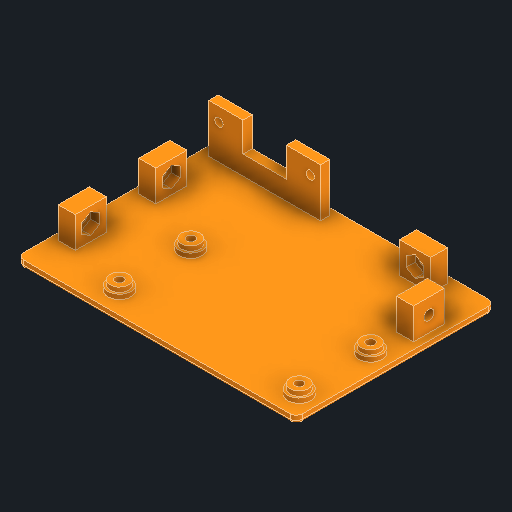
# Autodesk Inventor part: base_plate_compact_orange
Saved by Autodesk Inventor 2027.1 (Build 311270010, 270A)
## iProperties
Created: 2026-10-29
Part Number: base_plate_compact_orange
Material: Generic
Document SubType Name: Modeling
Designer: alexg
Density: 1 g/cm^3
Appearance: Orange
Description: COPY of base_plate_compact, orange: through bolts + hex nuts; back side +4 mm to match the frame copy (USB socket bracket + tab B moved with the wall)
Mass: 17.4421 g
Surface Area: 151.967 cm^2
Volume: 17.4421 cm^3
Author: alexg
Autodesk Inventor part; units mm, degrees
ref_plane "Work Plane1" through (0, -31.66, 0) normal (0, 1, 0) x (-1, 0, 0)
sketch "Plate sketch" plane through (0, -31.66, 0) normal (0, 1, 0) x (-1, 0, 0)
  line L0 (45, -30) -> (-45, -30)
  line L1 (-45, -30) -> (-45, 30)
  line L2 (-45, 30) -> (45, 30)
  line L3 (45, 30) -> (45, -30)
  constraints: 8 end point, 2 parallel, 1 horizontal, 1 perpendicular
extrude "Plate" add sketch "Plate sketch" against normal blind 2.5
ref_plane "Work Plane2" through (0, -31.66, 0) normal (0, 1, 0) x (-1, 0, 0)
sketch "Pi standoffs sketch" plane through (0, -31.66, 0) normal (0, 1, 0) x (-1, 0, 0)
  circle A0 centre (-38.97, 0.03) radius 3
  circle A1 centre (19.03, 0.03) radius 3
  circle A2 centre (-38.97, 23.03) radius 3
  circle A3 centre (19.03, 23.03) radius 3
  constraints: 4 centre point
extrude "Pi standoffs" add sketch "Pi standoffs sketch" along normal blind 3
ref_plane "Work Plane11" through (0, -31.66, 0) normal (0, 1, 0) x (-1, 0, 0)
sketch "Pi standoff feet (cover the nut pockets) sketch" plane through (0, -31.66, 0) normal (0, 1, 0) x (-1, 0, 0)
  circle A0 centre (-38.97, 0.03) radius 3.7
  circle A1 centre (19.03, 0.03) radius 3.7
  circle A2 centre (-38.97, 23.03) radius 3.7
  circle A3 centre (19.03, 23.03) radius 3.7
  constraints: 4 centre point
extrude "Pi standoff feet (cover the nut pockets)" add sketch "Pi standoff feet (cover the nut pockets) sketch" along normal blind 1.5
ref_plane "Work Plane3" through (0, -28.66, 0) normal (0, 1, 0) x (-1, 0, 0)
sketch "M2.5 insert holes (Pi) sketch" plane through (0, -28.66, 0) normal (0, 1, 0) x (-1, 0, 0)
  circle A0 centre (-38.97, 0.03) radius 1.35
  circle A1 centre (19.03, 0.03) radius 1.35
  circle A2 centre (-38.97, 23.03) radius 1.35
  circle A3 centre (19.03, 23.03) radius 1.35
  constraints: 4 centre point
extrude "M2.5 bolt holes (Pi, 2.7 through)" cut sketch "M2.5 insert holes (Pi) sketch" against normal blind 6
ref_plane "Work Plane4" through (0, -31.66, 0) normal (0, 1, 0) x (-1, 0, 0)
sketch "Screw tabs sketch" plane through (0, -31.66, 0) normal (0, 1, 0) x (-1, 0, 0)
  line L0 (42.8, -17) -> (39.8, -17)
  line L1 (39.8, -17) -> (39.8, -7)
  line L2 (39.8, -7) -> (42.8, -7)
  line L3 (42.8, -7) -> (42.8, -17)
  line L4 (42.8, 9) -> (39.8, 9)
  line L5 (39.8, 9) -> (39.8, 19)
  line L6 (39.8, 19) -> (42.8, 19)
  line L7 (42.8, 19) -> (42.8, 9)
  line L8 (-39.8, -20) -> (-42.8, -20)
  line L9 (-42.8, -20) -> (-42.8, -10)
  line L10 (-42.8, -10) -> (-39.8, -10)
  line L11 (-39.8, -10) -> (-39.8, -20)
  line L12 (-22, -27.8) -> (-32, -27.8)
  line L13 (-32, -27.8) -> (-32, -24.8)
  line L14 (-32, -24.8) -> (-22, -24.8)
  line L15 (-22, -24.8) -> (-22, -27.8)
  constraints: 32 end point, 8 parallel, 4 horizontal, 4 perpendicular
extrude "Screw tabs" add sketch "Screw tabs sketch" along normal blind 10
ref_plane "Work Plane12" through (0, -31.66, 0) normal (0, 1, 0) x (-1, 0, 0)
sketch "Screw tabs thickened to 5.5 (nut pockets) sketch" plane through (0, -31.66, 0) normal (0, 1, 0) x (-1, 0, 0)
  line L0 (39.8, -17) -> (37.3, -17)
  line L1 (37.3, -17) -> (37.3, -7)
  line L2 (37.3, -7) -> (39.8, -7)
  line L3 (39.8, -7) -> (39.8, -17)
  line L4 (39.8, 9) -> (37.3, 9)
  line L5 (37.3, 9) -> (37.3, 19)
  line L6 (37.3, 19) -> (39.8, 19)
  line L7 (39.8, 19) -> (39.8, 9)
  line L8 (-37.3, -20) -> (-39.8, -20)
  line L9 (-39.8, -20) -> (-39.8, -10)
  line L10 (-39.8, -10) -> (-37.3, -10)
  line L11 (-37.3, -10) -> (-37.3, -20)
  line L12 (-22, -24.8) -> (-32, -24.8)
  line L13 (-32, -24.8) -> (-32, -22.3)
  line L14 (-32, -22.3) -> (-22, -22.3)
  line L15 (-22, -22.3) -> (-22, -24.8)
  constraints: 32 end point, 8 parallel, 4 horizontal, 4 perpendicular
extrude "Screw tabs thickened to 5.5 (nut pockets)" add sketch "Screw tabs thickened to 5.5 (nut pockets) sketch" along normal blind 10
ref_plane "Work Plane5" through (-43.5, 0, 0) normal (1, 0, 0) x (0, 1, 0)
sketch "M3 insert holes L sketch" plane through (-43.5, 0, 0) normal (1, 0, 0) x (0, 1, 0)
  circle A0 centre (-26.66, -12) radius 1.6
  circle A1 centre (-26.66, 14) radius 1.6
  constraints: 2 centre point
extrude "M3 bolt holes L (3.2)" cut sketch "M3 insert holes L sketch" along normal blind 7
ref_plane "Work Plane6" through (43.5, 0, 0) normal (1, 0, 0) x (0, 1, 0)
sketch "M3 insert holes R sketch" plane through (43.5, 0, 0) normal (1, 0, 0) x (0, 1, 0)
  circle A0 centre (-26.66, -15) radius 1.6
  constraints: 1 centre point
extrude "M3 bolt holes R (3.2)" cut sketch "M3 insert holes R sketch" against normal blind 7
ref_plane "Work Plane7" through (0, 0, -28.5) normal (0, 0, 1) x (1, 0, 0)
sketch "M3 insert hole B sketch" plane through (0, 0, -28.5) normal (0, 0, 1) x (1, 0, 0)
  circle A0 centre (27, -26.66) radius 1.6
  constraints: 1 centre point
extrude "M3 bolt hole B (3.2)" cut sketch "M3 insert hole B sketch" along normal blind 7
ref_plane "Work Plane8" through (0, -31.66, 0) normal (0, 1, 0) x (-1, 0, 0)
sketch "USB socket bracket sketch" plane through (0, -31.66, 0) normal (0, 1, 0) x (-1, 0, 0)
  line L0 (40, -27.8) -> (8, -27.8)
  line L1 (8, -27.8) -> (8, -24.8)
  line L2 (8, -24.8) -> (40, -24.8)
  line L3 (40, -24.8) -> (40, -27.8)
  constraints: 8 end point, 2 parallel, 1 horizontal, 1 perpendicular
extrude "USB socket bracket" [suppressed]
ref_plane "Work Plane9" through (0, 0, -27.8) normal (0, 0, 1) x (1, 0, 0)
sketch "External plug opening sketch" plane through (0, 0, -27.8) normal (0, 0, 1) x (1, 0, 0)
  line L0 (-31, -30.84) -> (-17, -30.84)
  line L1 (-17, -30.84) -> (-17, -19.84)
  line L2 (-17, -19.84) -> (-31, -19.84)
  line L3 (-31, -19.84) -> (-31, -30.84)
  constraints: 8 end point, 2 parallel, 1 horizontal, 1 perpendicular
extrude "External plug opening" [suppressed]
ref_plane "Work Plane10" through (0, 0, -24.8) normal (0, 0, 1) x (1, 0, 0)
sketch "M2.5x3 insert holes (USB) sketch" plane through (0, 0, -24.8) normal (0, 0, 1) x (1, 0, 0)
  circle A0 centre (-36.5, -25.84) radius 1.35
  circle A1 centre (-11.5, -25.84) radius 1.35
  constraints: 2 centre point
extrude "M2.5 bolt holes (USB socket, 2.7)" [suppressed]
ref_plane "Work Plane13" through (0, -34.16, 0) normal (0, 1, 0) x (-1, 0, 0)
sketch "Pi nut pockets M2.5 (underside) sketch" plane through (0, -34.16, 0) normal (0, 1, 0) x (-1, 0, 0)
  line L0 (-41.9722, 0.03) -> (-40.4711, 2.63)
  line L1 (-40.4711, 2.63) -> (-37.4689, 2.63)
  line L2 (-37.4689, 2.63) -> (-35.9678, 0.03)
  line L3 (-35.9678, 0.03) -> (-37.4689, -2.57)
  line L4 (-37.4689, -2.57) -> (-40.4711, -2.57)
  line L5 (-40.4711, -2.57) -> (-41.9722, 0.03)
  line L6 (16.0278, 0.03) -> (17.5289, 2.63)
  line L7 (17.5289, 2.63) -> (20.5311, 2.63)
  line L8 (20.5311, 2.63) -> (22.0322, 0.03)
  line L9 (22.0322, 0.03) -> (20.5311, -2.57)
  line L10 (20.5311, -2.57) -> (17.5289, -2.57)
  line L11 (17.5289, -2.57) -> (16.0278, 0.03)
  line L12 (-41.9722, 23.03) -> (-40.4711, 25.63)
  line L13 (-40.4711, 25.63) -> (-37.4689, 25.63)
  line L14 (-37.4689, 25.63) -> (-35.9678, 23.03)
  line L15 (-35.9678, 23.03) -> (-37.4689, 20.43)
  line L16 (-37.4689, 20.43) -> (-40.4711, 20.43)
  line L17 (-40.4711, 20.43) -> (-41.9722, 23.03)
  line L18 (16.0278, 23.03) -> (17.5289, 25.63)
  line L19 (17.5289, 25.63) -> (20.5311, 25.63)
  line L20 (20.5311, 25.63) -> (22.0322, 23.03)
  line L21 (22.0322, 23.03) -> (20.5311, 20.43)
  line L22 (20.5311, 20.43) -> (17.5289, 20.43)
  line L23 (17.5289, 20.43) -> (16.0278, 23.03)
  constraints: 48 end point
extrude "Pi nut pockets M2.5 (underside)" cut sketch "Pi nut pockets M2.5 (underside) sketch" along normal blind 3.1
ref_plane "Work Plane14" through (-37.3, 0, 0) normal (1, 0, 0) x (0, 1, 0)
sketch "Base nut pockets M3 L sketch" plane through (-37.3, 0, 0) normal (1, 0, 0) x (0, 1, 0)
  line L0 (-23.3691, -12) -> (-25.0146, -14.85)
  line L1 (-25.0146, -14.85) -> (-28.3054, -14.85)
  line L2 (-28.3054, -14.85) -> (-29.9509, -12)
  line L3 (-29.9509, -12) -> (-28.3054, -9.15)
  line L4 (-28.3054, -9.15) -> (-25.0146, -9.15)
  line L5 (-25.0146, -9.15) -> (-23.3691, -12)
  line L6 (-23.3691, 14) -> (-25.0146, 11.15)
  line L7 (-25.0146, 11.15) -> (-28.3054, 11.15)
  line L8 (-28.3054, 11.15) -> (-29.9509, 14)
  line L9 (-29.9509, 14) -> (-28.3054, 16.85)
  line L10 (-28.3054, 16.85) -> (-25.0146, 16.85)
  line L11 (-25.0146, 16.85) -> (-23.3691, 14)
  constraints: 24 end point
extrude "Base nut pockets M3 L" cut sketch "Base nut pockets M3 L sketch" against normal blind 2.9
ref_plane "Work Plane15" through (37.3, 0, 0) normal (1, 0, 0) x (0, 1, 0)
sketch "Base nut pocket M3 R sketch" plane through (37.3, 0, 0) normal (1, 0, 0) x (0, 1, 0)
  line L0 (-23.3691, -15) -> (-25.0146, -17.85)
  line L1 (-25.0146, -17.85) -> (-28.3054, -17.85)
  line L2 (-28.3054, -17.85) -> (-29.9509, -15)
  line L3 (-29.9509, -15) -> (-28.3054, -12.15)
  line L4 (-28.3054, -12.15) -> (-25.0146, -12.15)
  line L5 (-25.0146, -12.15) -> (-23.3691, -15)
  constraints: 12 end point
extrude "Base nut pocket M3 R" cut sketch "Base nut pocket M3 R sketch" along normal blind 2.9
ref_plane "Work Plane16" through (0, 0, -22.3) normal (0, 0, 1) x (1, 0, 0)
sketch "Base nut pocket M3 B sketch" plane through (0, 0, -22.3) normal (0, 0, 1) x (1, 0, 0)
  line L0 (27, -23.3691) -> (24.15, -25.0146)
  line L1 (24.15, -25.0146) -> (24.15, -28.3054)
  line L2 (24.15, -28.3054) -> (27, -29.9509)
  line L3 (27, -29.9509) -> (29.85, -28.3054)
  line L4 (29.85, -28.3054) -> (29.85, -25.0146)
  line L5 (29.85, -25.0146) -> (27, -23.3691)
  constraints: 12 end point
extrude "Base nut pocket M3 B" cut sketch "Base nut pocket M3 B sketch" against normal blind 2.9
ref_plane "Work Plane17" through (-36.5, 0, 0) normal (1, 0, 0) x (0, 1, 0)
sketch "USB countersink 1 (M2.5 flat head, outside face) sketch" plane through (-36.5, 0, 0) normal (1, 0, 0) x (0, 1, 0)
  line L0 (-25.84, -26.65) -> (-25.84, -28)
  line L1 (-25.84, -28) -> (-23.14, -28)
  line L2 (-23.14, -28) -> (-24.49, -26.65)
  line L3 (-24.49, -26.65) -> (-25.84, -26.65)
  constraints: 8 end point
revolve "USB countersink 1 (M2.5 flat head, outside face)" [suppressed]
ref_plane "Work Plane18" through (-11.5, 0, 0) normal (1, 0, 0) x (0, 1, 0)
sketch "USB countersink 2 (M2.5 flat head, outside face) sketch" plane through (-11.5, 0, 0) normal (1, 0, 0) x (0, 1, 0)
  line L0 (-25.84, -26.65) -> (-25.84, -28)
  line L1 (-25.84, -28) -> (-23.14, -28)
  line L2 (-23.14, -28) -> (-24.49, -26.65)
  line L3 (-24.49, -26.65) -> (-25.84, -26.65)
  constraints: 8 end point
revolve "USB countersink 2 (M2.5 flat head, outside face)" [suppressed]
ref_plane "Work Plane19" through (0, -31.66, 0) normal (0, 1, 0) x (-1, 0, 0)
sketch "USB socket bracket v2 (36 long, top y -16) sketch" plane through (0, -31.66, 0) normal (0, 1, 0) x (-1, 0, 0)
  line L0 (42, -27.8) -> (6, -27.8)
  line L1 (6, -27.8) -> (6, -24.8)
  line L2 (6, -24.8) -> (42, -24.8)
  line L3 (42, -24.8) -> (42, -27.8)
  constraints: 8 end point, 2 parallel, 1 horizontal, 1 perpendicular
extrude "USB socket bracket v2 (36 long, top y -16)" [suppressed]
ref_plane "Work Plane20" through (0, 0, -27.8) normal (0, 0, 1) x (1, 0, 0)
sketch "External plug opening v2 (open top) sketch" plane through (0, 0, -27.8) normal (0, 0, 1) x (1, 0, 0)
  line L0 (-31, -25.5) -> (-17, -25.5)
  line L1 (-17, -25.5) -> (-17, -14)
  line L2 (-17, -14) -> (-31, -14)
  line L3 (-31, -14) -> (-31, -25.5)
  constraints: 8 end point, 2 parallel, 1 horizontal, 1 perpendicular
extrude "External plug opening v2 (open top)" [suppressed]
ref_plane "Work Plane21" through (0, 0, -24.8) normal (0, 0, 1) x (1, 0, 0)
sketch "M2.5 bolt holes v2 (USB socket, 2.7, 29.5 pitch) sketch" plane through (0, 0, -24.8) normal (0, 0, 1) x (1, 0, 0)
  circle A0 centre (-38.75, -20.5) radius 1.35
  circle A1 centre (-9.25, -20.5) radius 1.35
  constraints: 2 centre point
extrude "M2.5 bolt holes v2 (USB socket, 2.7, 29.5 pitch)" [suppressed]
ref_plane "Work Plane22" through (-38.75, 0, 0) normal (1, 0, 0) x (0, 1, 0)
sketch "USB countersink v2 1 (M2.5 flat head, outside face) sketch" plane through (-38.75, 0, 0) normal (1, 0, 0) x (0, 1, 0)
  line L0 (-20.5, -26.65) -> (-20.5, -28)
  line L1 (-20.5, -28) -> (-17.8, -28)
  line L2 (-17.8, -28) -> (-19.15, -26.65)
  line L3 (-19.15, -26.65) -> (-20.5, -26.65)
  constraints: 8 end point
revolve "USB countersink v2 1 (M2.5 flat head, outside face)" [suppressed]
ref_plane "Work Plane23" through (-9.25, 0, 0) normal (1, 0, 0) x (0, 1, 0)
sketch "USB countersink v2 2 (M2.5 flat head, outside face) sketch" plane through (-9.25, 0, 0) normal (1, 0, 0) x (0, 1, 0)
  line L0 (-20.5, -26.65) -> (-20.5, -28)
  line L1 (-20.5, -28) -> (-17.8, -28)
  line L2 (-17.8, -28) -> (-19.15, -26.65)
  line L3 (-19.15, -26.65) -> (-20.5, -26.65)
  constraints: 8 end point
revolve "USB countersink v2 2 (M2.5 flat head, outside face)" [suppressed]
ref_plane "Work Plane24" through (0, -31.66, 0) normal (0, 1, 0) x (-1, 0, 0)
sketch "Back +4: plate extension (z -34..-30) sketch" plane through (0, -31.66, 0) normal (0, 1, 0) x (-1, 0, 0)
  line L0 (45, -34) -> (-45, -34)
  line L1 (-45, -34) -> (-45, -30)
  line L2 (-45, -30) -> (45, -30)
  line L3 (45, -30) -> (45, -34)
  constraints: 8 end point, 2 parallel, 1 horizontal, 1 perpendicular
extrude "Back +4: plate extension (z -34..-30)" add sketch "Back +4: plate extension (z -34..-30) sketch" against normal blind 2.5
ref_plane "Work Plane25" through (0, -31.66, 0) normal (0, 1, 0) x (-1, 0, 0)
sketch "Back +4: screw tab B moved (z -31.8..-26.3) sketch" plane through (0, -31.66, 0) normal (0, 1, 0) x (-1, 0, 0)
  line L0 (-22, -31.8) -> (-32, -31.8)
  line L1 (-32, -31.8) -> (-32, -26.3)
  line L2 (-32, -26.3) -> (-22, -26.3)
  line L3 (-22, -26.3) -> (-22, -31.8)
  constraints: 8 end point, 2 parallel, 1 horizontal, 1 perpendicular
extrude "Back +4: screw tab B moved (z -31.8..-26.3)" add sketch "Back +4: screw tab B moved (z -31.8..-26.3) sketch" along normal blind 10
ref_plane "Work Plane26" through (0, -31.66, 0) normal (0, 1, 0) x (-1, 0, 0)
sketch "Back +4: old screw tab B removed sketch" plane through (0, -31.66, 0) normal (0, 1, 0) x (-1, 0, 0)
  line L0 (-22, -26.3) -> (-32, -26.3)
  line L1 (-32, -26.3) -> (-32, -22.3)
  line L2 (-32, -22.3) -> (-22, -22.3)
  line L3 (-22, -22.3) -> (-22, -26.3)
  constraints: 8 end point, 2 parallel, 1 horizontal, 1 perpendicular
extrude "Back +4: old screw tab B removed" cut sketch "Back +4: old screw tab B removed sketch" along normal blind 10
ref_plane "Work Plane27" through (0, 0, -32.5) normal (0, 0, 1) x (1, 0, 0)
sketch "Back +4: M3 bolt hole B (3.2) sketch" plane through (0, 0, -32.5) normal (0, 0, 1) x (1, 0, 0)
  circle A0 centre (27, -26.66) radius 1.6
  constraints: 1 centre point
extrude "Back +4: M3 bolt hole B (3.2)" cut sketch "Back +4: M3 bolt hole B (3.2) sketch" along normal blind 7
ref_plane "Work Plane28" through (0, 0, -26.3) normal (0, 0, 1) x (1, 0, 0)
sketch "Back +4: base nut pocket M3 B sketch" plane through (0, 0, -26.3) normal (0, 0, 1) x (1, 0, 0)
  line L0 (27, -23.37) -> (24.15, -25.01)
  line L1 (24.15, -25.01) -> (24.15, -28.31)
  line L2 (24.15, -28.31) -> (27, -29.95)
  line L3 (27, -29.95) -> (29.85, -28.31)
  line L4 (29.85, -28.31) -> (29.85, -25.01)
  line L5 (29.85, -25.01) -> (27, -23.37)
  constraints: 12 end point
extrude "Back +4: base nut pocket M3 B" cut sketch "Back +4: base nut pocket M3 B sketch" against normal blind 2.9
ref_plane "Work Plane29" through (0, -31.66, 0) normal (0, 1, 0) x (-1, 0, 0)
sketch "USB socket bracket v3 (back +4, z -31.8..-28.8) sketch" plane through (0, -31.66, 0) normal (0, 1, 0) x (-1, 0, 0)
  line L0 (42, -31.8) -> (6, -31.8)
  line L1 (6, -31.8) -> (6, -28.8)
  line L2 (6, -28.8) -> (42, -28.8)
  line L3 (42, -28.8) -> (42, -31.8)
  constraints: 8 end point, 2 parallel, 1 horizontal, 1 perpendicular
extrude "USB socket bracket v3 (back +4, z -31.8..-28.8)" add sketch "USB socket bracket v3 (back +4, z -31.8..-28.8) sketch" along normal blind 15.66
ref_plane "Work Plane30" through (0, 0, -31.8) normal (0, 0, 1) x (1, 0, 0)
sketch "External plug opening v3 (open top) sketch" plane through (0, 0, -31.8) normal (0, 0, 1) x (1, 0, 0)
  line L0 (-31, -25.5) -> (-17, -25.5)
  line L1 (-17, -25.5) -> (-17, -14)
  line L2 (-17, -14) -> (-31, -14)
  line L3 (-31, -14) -> (-31, -25.5)
  constraints: 8 end point, 2 parallel, 1 horizontal, 1 perpendicular
extrude "External plug opening v3 (open top)" cut sketch "External plug opening v3 (open top) sketch" along normal blind 3
ref_plane "Work Plane31" through (0, 0, -28.8) normal (0, 0, 1) x (1, 0, 0)
sketch "M2.5 bolt holes v3 (USB socket, 2.7, 29.5 pitch) sketch" plane through (0, 0, -28.8) normal (0, 0, 1) x (1, 0, 0)
  circle A0 centre (-38.75, -20.5) radius 1.35
  circle A1 centre (-9.25, -20.5) radius 1.35
  constraints: 2 centre point
extrude "M2.5 bolt holes v3 (USB socket, 2.7, 29.5 pitch)" cut sketch "M2.5 bolt holes v3 (USB socket, 2.7, 29.5 pitch) sketch" against normal blind 3.5
ref_plane "Work Plane32" through (-38.75, 0, 0) normal (1, 0, 0) x (0, 1, 0)
sketch "USB countersink v3 1 (M2.5 flat head, outside face) sketch" plane through (-38.75, 0, 0) normal (1, 0, 0) x (0, 1, 0)
  line L0 (-20.5, -30.65) -> (-20.5, -32)
  line L1 (-20.5, -32) -> (-17.8, -32)
  line L2 (-17.8, -32) -> (-19.15, -30.65)
  line L3 (-19.15, -30.65) -> (-20.5, -30.65)
  constraints: 8 end point
revolve "USB countersink v3 1 (M2.5 flat head, outside face)" cut sketch "USB countersink v3 1 (M2.5 flat head, outside face) sketch" angle 360 about axis through (-38.75, -20.5, -30.65) along (0, 0, -1)
ref_plane "Work Plane33" through (-9.25, 0, 0) normal (1, 0, 0) x (0, 1, 0)
sketch "USB countersink v3 2 (M2.5 flat head, outside face) sketch" plane through (-9.25, 0, 0) normal (1, 0, 0) x (0, 1, 0)
  line L0 (-20.5, -30.65) -> (-20.5, -32)
  line L1 (-20.5, -32) -> (-17.8, -32)
  line L2 (-17.8, -32) -> (-19.15, -30.65)
  line L3 (-19.15, -30.65) -> (-20.5, -30.65)
  constraints: 8 end point
revolve "USB countersink v3 2 (M2.5 flat head, outside face)" cut sketch "USB countersink v3 2 (M2.5 flat head, outside face) sketch" angle 360 about axis through (-9.25, -20.5, -30.65) along (0, 0, -1)
fillet "Handling rounds: vertical outer corners R2 (4 edges)" radius 2 4 edges at (45, -32.91, -34) (-45, -32.91, -34) (-45, -32.91, 30) (45, -32.91, 30)
fillet "Handling rounds: bottom edge R1 (8 edges)" radius 1 5 edges at (44.4142, -34.16, 29.4142) (0, -34.16, 30) (-44.4142, -34.16, 29.4142) (-45, -34.16, -2) (0, -34.16, -34)
body "Solid1"
